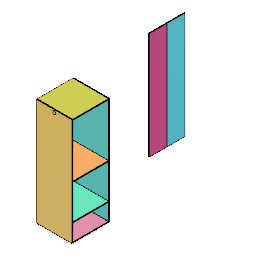
mini wardrobe (Autodesk Fusion 360 design; units mm, degrees)
Autodesk Fusion 360 part; units mm, degrees
sketch "Sketch1" plane through (0, 0, 0) normal (0, 0, 1) x (1, 0, 0) in component "Component"
  line L0 (0, 0) -> (610, 0)
  line L1 (610, 0) -> (610, 1830)
  line L2 (610, 1830) -> (0, 1830)
  line L3 (0, 1830) -> (0, 0)
  dimension "d1" = 610
  dimension "d2" = 1830
  constraint horizontal L0
  constraint vertical L1
  constraint horizontal L2
  constraint vertical L3
  constraint coincident L0.start L3.end
  measures "d1" distance of L0.start L0.end
  measures "d2" distance of L0.start L2.end
extrude "Extrude1" add sketch "Sketch1" against normal blind 15 makes body 1 in component "Component"
copy_body "CopyPasteBodies1" bodies 1 makes body 2 in component "Component"
move_body "Move1" bodies 2 to x (1, 0, 0) y (0, 1, 0) z (0, 0, 1) at (0, 0, -1200) in component "Component"
copy_body "CopyPasteBodies2" bodies 1 makes body 3 in component "Component"
move_body "Move2" bodies 3 to x (0, 0, 1) y (0, 1, 0) z (-1, 0, 0) at (-15, 0, -915) in component "Component"
copy_body "Body->Comp1" bodies 1 removing the originals makes body 4 in component "Component'"
copy_body "Body->Comp2" bodies 2 removing the originals makes body 5 in component "Component''"
copy_body "Body->Comp3" bodies 3 removing the originals makes body 6 in component "Component'''"
sketch "Sketch1 (2)" plane through (0, 0, 0) normal (0, 1, 0) x (1, 0, 0) in component "Component''''"
  line L0 (0, 0) -> (610, 0)
  line L1 (610, 0) -> (610, 610)
  line L2 (610, 610) -> (0, 610)
  line L3 (0, 610) -> (0, 0)
  dimension "d5" = 610
  dimension "d6" = 610
  constraint horizontal L0
  constraint vertical L1
  constraint horizontal L2
  constraint vertical L3
  constraint coincident L0.start L3.end
  measures "d5" distance of L0.start L0.end
  measures "d6" distance of L0.start L2.end
extrude "Extrude1'" add sketch "Sketch1 (2)" along normal blind 15 separate body makes body 7 in component "Component''''"
copy_body "CopyPasteBodies1'" bodies 7 makes body 8 in component "Component''''"
move_body "Move1'" bodies 8 to x (1, 0, 0) y (0, 1, 0) z (0, 0, 1) at (0, 900, 0) in component "Component''''"
copy_body "CopyPasteBodies2'" bodies 7 makes body 9 in component "Component''''"
move_body "Move2'" bodies 9 to x (1, 0, 0) y (0, 1, 0) z (0, 0, 1) at (0, 300, 0) in component "Component''''"
copy_body "CopyPasteBodies3" bodies 7 makes body 10 in component "Component''''"
move_body "Move3" bodies 10 to x (1, 0, 0) y (0, 1, 0) z (0, 0, 1) at (0, 1815, 0) in component "Component''''"
copy_body "Body->Comp1'" bodies 7 removing the originals makes body 11 in component "Component'''''"
copy_body "Body->Comp2'" bodies 8 removing the originals makes body 12 in component "Component''''''"
copy_body "Body->Comp3'" bodies 9 removing the originals makes body 13 in component "Component'''''''"
copy_body "Body->Comp4" bodies 10 removing the originals makes body 14 in component "Component''''''''"
sketch "Sketch2" plane through (0, 0, -570.2662) normal (0, 0, 1) x (1, 0, 0) in component "Component"
  line L0 (-29.0855, 1804.3517) -> (-29.0855, -25.6483)
  line L1 (-29.0855, -25.6483) -> (580.9145, -25.6483)
  line L2 (580.9145, -25.6483) -> (580.9145, 1804.3517)
  line L3 (580.9145, 1804.3517) -> (-29.0855, 1804.3517)
  line L4 (-29.0855, 1804.3517) -> (580.9145, 1804.3517)
  line L5 (580.9145, 1804.3517) -> (580.9145, 1704.3517)
  line L6 (580.9145, 1704.3517) -> (-29.0855, 1704.3517)
  line L7 (-29.0855, 1704.3517) -> (-29.0855, 1804.3517)
  line L8 (275.9145, 1804.3517) -> (275.9145, 1704.3517)
  circle A0 centre (275.9145, 1754.3517) radius 25
  dimension "d17" = 100
  dimension "d18" = 50
  constraint horizontal L4
  constraint vertical L5
  constraint horizontal L6
  constraint vertical L7
  constraint coincident L0.start L3.end
  constraint midpoint L3 L8.start
  constraint midpoint L6 L8.end
  constraint perpendicular L6 L8
  constraint midpoint L8 A0.centre
  measures "d17" distance of L0.start L6.end
  measures "d18" diameter of A0
extrude "Extrude1''" cut sketch "Sketch2" against normal blind 10 contours L8 A0 | L8 A0 sketch seen with x (1, 0, 0) y (0, 1, 0) z (0, 0, 1) at (29.0855, 25.6483, -629.7338) bodies 5 in component "Component''"
extrude "Extrude1'''" cut sketch "Sketch2" along normal blind 620 contours L8 A0 | L8 A0 sketch seen with x (1, 0, 0) y (0, 1, 0) z (0, 0, 1) at (29.0855, 25.6483, -54.7338) bodies 4 in component "Component'"
extrude "Extrude1''''" add 1 faces at (312.5081, 1778.8683, -1210) faces seen with x (1, 0, 0) y (0, 1, 0) z (0, 0, 1) at (-29.0855, -25.6483, 629.7338) along direction (0, 0, 1) blind 630 separate body on bodies 5 makes body 15 in component "Component'''''''''"
sketch "Sketch1 (3)" plane through (-726.8551, 0, 0) normal (1, 0, 0) x (0, 0, -1)
  line L0 (1765.3242, -123.4691) -> (1765.3242, 1706.5309)
  line L1 (1765.3242, 1706.5309) -> (1155.3242, 1706.5309)
  line L2 (1155.3242, 1706.5309) -> (1155.3242, -123.4691)
  line L3 (1155.3242, -123.4691) -> (1765.3242, -123.4691)
  line L4 (1155.3242, 1706.5309) -> (1765.3242, 1706.5309)
  line L5 (1765.3242, 1706.5309) -> (1765.3242, 1570.4671)
  line L6 (1765.3242, 1570.4671) -> (1155.3242, 1570.4671)
  line L7 (1155.3242, 1570.4671) -> (1155.3242, 1706.5309)
  line L8 (1460.3242, 1706.5309) -> (1460.3242, -123.4691)
  constraint horizontal L4
  constraint vertical L5
  constraint horizontal L6
  constraint vertical L7
  constraint coincident L0 L5.end
  constraint coincident L1.end L2.start
  constraint midpoint L1 L8.start
  constraint midpoint L3 L8.end
split "Split1" by curves path "Sketch1 (3)" along L8 path seen with x (1, 0, 0) y (0, 1, 0) z (0, 0, 1) at (726.8551, 123.4691, 850.3243) bodies 6 makes body 16 at (-15, 610, -508.3333) in component "Component'''"
copy_body "Body->Comp1''" bodies 6 removing the originals makes body 17 in component "Component''''''''''"
copy_body "Body->Comp2''" bodies 16 removing the originals makes body 18 in component "Component'''''''''''"
component "Component" placed x (1, 0, 0) y (0, 1, 0) z (0, 0, 1) at (0, 0, 0)
component "Component''''" placed x (1, 0, 0) y (0, 1, 0) z (0, 0, 1) at (-29.0855, -25.6483, 39.7338)
component "Component'''''''''" placed x (1, 0, 0) y (0, 1, 0) z (0, 0, 1) at (0, 0, 0)
component "Component'" placed x (1, 0, 0) y (0, 1, 0) z (0, 0, 1) at (-29.0855, -25.6483, 54.7338) in component "Component"
component "Component''" placed x (1, 0, 0) y (0, 1, 0) z (0, 0, 1) at (-29.0855, -25.6483, 629.7338) in component "Component"
component "Component'''" placed x (1, 0, 0) y (0, 1, 0) z (0, 0, 1) at (-726.8551, -123.4691, -850.3243) in component "Component"
component "Component''''''''''" placed x (1, 0, 0) y (0, 1, 0) z (0, 0, 1) at (0, 0, 0) in component "Component'''"
component "Component'''''''''''" placed x (1, 0, 0) y (0, 1, 0) z (0, 0, 1) at (0, 0, 0) in component "Component'''"
component "Component'''''" placed x (1, 0, 0) y (0, 1, 0) z (0, 0, 1) at (0, 0, 0) in component "Component''''"
component "Component''''''" placed x (1, 0, 0) y (0, 1, 0) z (0, 0, 1) at (0, 0, 0) in component "Component''''"
component "Component'''''''" placed x (1, 0, 0) y (0, 1, 0) z (0, 0, 1) at (0, 0, 0) in component "Component''''"
component "Component''''''''" placed x (1, 0, 0) y (0, 1, 0) z (0, 0, 1) at (0, 0, 0) in component "Component''''"
